Autodesk Fusion 360 part; units mm, degrees
(part 2 of 5)
sketch "Receiver conveyor side beam sketch (1)" plane through (0, 0, -180) normal (0, 0, 1) x (1, 0, 0) in component "MM28 Sliding receiver conveyor"
  line L0 (-2100, 164) -> (-930, 164)
  line L1 (-930, 164) -> (-930, 186)
  line L2 (-930, 186) -> (-2100, 186)
  line L3 (-2100, 186) -> (-2100, 164)
extrude "Receiver conveyor side beam (1)" add sketch "Receiver conveyor side beam sketch (1)" along normal blind 32 separate body makes body 68 in component "MM28 Sliding receiver conveyor"
ref_plane "WorkPlane3" through (0, -195, 0) normal (0, 1, 0) x (0, 0, 1) in component "MM28 Sliding receiver conveyor"
sketch "Receiver conveyor roller sketch" plane through (0, -195, 0) normal (0, 1, 0) x (1, 0, 0) in component "MM28 Sliding receiver conveyor"
  circle A0 centre (-2085, 136) radius 8
extrude "Receiver conveyor roller" add sketch "Receiver conveyor roller sketch" along normal blind 390 separate body makes body 69 in component "MM28 Sliding receiver conveyor"
ref_plane "WorkPlane4" through (0, -195, 0) normal (0, 1, 0) x (0, 0, 1) in component "MM28 Sliding receiver conveyor"
sketch "Receiver conveyor roller sketch (1)" plane through (0, -195, 0) normal (0, 1, 0) x (1, 0, 0) in component "MM28 Sliding receiver conveyor"
  circle A0 centre (-2025, 136) radius 8
extrude "Receiver conveyor roller (1)" add sketch "Receiver conveyor roller sketch (1)" along normal blind 390 separate body makes body 70 in component "MM28 Sliding receiver conveyor"
ref_plane "WorkPlane5" through (0, -195, 0) normal (0, 1, 0) x (0, 0, 1) in component "MM28 Sliding receiver conveyor"
sketch "Receiver conveyor roller sketch (2)" plane through (0, -195, 0) normal (0, 1, 0) x (1, 0, 0) in component "MM28 Sliding receiver conveyor"
  circle A0 centre (-1965, 136) radius 8
extrude "Receiver conveyor roller (2)" add sketch "Receiver conveyor roller sketch (2)" along normal blind 390 separate body makes body 71 in component "MM28 Sliding receiver conveyor"
ref_plane "WorkPlane6" through (0, -195, 0) normal (0, 1, 0) x (0, 0, 1) in component "MM28 Sliding receiver conveyor"
sketch "Receiver conveyor roller sketch (3)" plane through (0, -195, 0) normal (0, 1, 0) x (1, 0, 0) in component "MM28 Sliding receiver conveyor"
  circle A0 centre (-1905, 136) radius 8
extrude "Receiver conveyor roller (3)" add sketch "Receiver conveyor roller sketch (3)" along normal blind 390 separate body makes body 72 in component "MM28 Sliding receiver conveyor"
ref_plane "WorkPlane7" through (0, -195, 0) normal (0, 1, 0) x (0, 0, 1) in component "MM28 Sliding receiver conveyor"
sketch "Receiver conveyor roller sketch (4)" plane through (0, -195, 0) normal (0, 1, 0) x (1, 0, 0) in component "MM28 Sliding receiver conveyor"
  circle A0 centre (-1845, 136) radius 8
extrude "Receiver conveyor roller (4)" add sketch "Receiver conveyor roller sketch (4)" along normal blind 390 separate body makes body 73 in component "MM28 Sliding receiver conveyor"
ref_plane "WorkPlane8" through (0, -195, 0) normal (0, 1, 0) x (0, 0, 1) in component "MM28 Sliding receiver conveyor"
sketch "Receiver conveyor roller sketch (5)" plane through (0, -195, 0) normal (0, 1, 0) x (1, 0, 0) in component "MM28 Sliding receiver conveyor"
  circle A0 centre (-1785, 136) radius 8
extrude "Receiver conveyor roller (5)" add sketch "Receiver conveyor roller sketch (5)" along normal blind 390 separate body makes body 74 in component "MM28 Sliding receiver conveyor"
ref_plane "WorkPlane9" through (0, -195, 0) normal (0, 1, 0) x (0, 0, 1) in component "MM28 Sliding receiver conveyor"
sketch "Receiver conveyor roller sketch (6)" plane through (0, -195, 0) normal (0, 1, 0) x (1, 0, 0) in component "MM28 Sliding receiver conveyor"
  circle A0 centre (-1725, 136) radius 8
extrude "Receiver conveyor roller (6)" add sketch "Receiver conveyor roller sketch (6)" along normal blind 390 separate body makes body 75 in component "MM28 Sliding receiver conveyor"
ref_plane "WorkPlane10" through (0, -195, 0) normal (0, 1, 0) x (0, 0, 1) in component "MM28 Sliding receiver conveyor"
sketch "Receiver conveyor roller sketch (7)" plane through (0, -195, 0) normal (0, 1, 0) x (1, 0, 0) in component "MM28 Sliding receiver conveyor"
  circle A0 centre (-1665, 136) radius 8
extrude "Receiver conveyor roller (7)" add sketch "Receiver conveyor roller sketch (7)" along normal blind 390 separate body makes body 76 in component "MM28 Sliding receiver conveyor"
ref_plane "WorkPlane11" through (0, -195, 0) normal (0, 1, 0) x (0, 0, 1) in component "MM28 Sliding receiver conveyor"
sketch "Receiver conveyor roller sketch (8)" plane through (0, -195, 0) normal (0, 1, 0) x (1, 0, 0) in component "MM28 Sliding receiver conveyor"
  circle A0 centre (-1605, 136) radius 8
extrude "Receiver conveyor roller (8)" add sketch "Receiver conveyor roller sketch (8)" along normal blind 390 separate body makes body 77 in component "MM28 Sliding receiver conveyor"
ref_plane "WorkPlane12" through (0, -195, 0) normal (0, 1, 0) x (0, 0, 1) in component "MM28 Sliding receiver conveyor"
sketch "Receiver conveyor roller sketch (9)" plane through (0, -195, 0) normal (0, 1, 0) x (1, 0, 0) in component "MM28 Sliding receiver conveyor"
  circle A0 centre (-1545, 136) radius 8
extrude "Receiver conveyor roller (9)" add sketch "Receiver conveyor roller sketch (9)" along normal blind 390 separate body makes body 78 in component "MM28 Sliding receiver conveyor"
ref_plane "WorkPlane13" through (0, -195, 0) normal (0, 1, 0) x (0, 0, 1) in component "MM28 Sliding receiver conveyor"
sketch "Receiver conveyor roller sketch (10)" plane through (0, -195, 0) normal (0, 1, 0) x (1, 0, 0) in component "MM28 Sliding receiver conveyor"
  circle A0 centre (-1485, 136) radius 8
extrude "Receiver conveyor roller (10)" add sketch "Receiver conveyor roller sketch (10)" along normal blind 390 separate body makes body 79 in component "MM28 Sliding receiver conveyor"
ref_plane "WorkPlane14" through (0, -195, 0) normal (0, 1, 0) x (0, 0, 1) in component "MM28 Sliding receiver conveyor"
sketch "Receiver conveyor roller sketch (11)" plane through (0, -195, 0) normal (0, 1, 0) x (1, 0, 0) in component "MM28 Sliding receiver conveyor"
  circle A0 centre (-1425, 136) radius 8
extrude "Receiver conveyor roller (11)" add sketch "Receiver conveyor roller sketch (11)" along normal blind 390 separate body makes body 80 in component "MM28 Sliding receiver conveyor"
ref_plane "WorkPlane15" through (0, -195, 0) normal (0, 1, 0) x (0, 0, 1) in component "MM28 Sliding receiver conveyor"
sketch "Receiver conveyor roller sketch (12)" plane through (0, -195, 0) normal (0, 1, 0) x (1, 0, 0) in component "MM28 Sliding receiver conveyor"
  circle A0 centre (-1365, 136) radius 8
extrude "Receiver conveyor roller (12)" add sketch "Receiver conveyor roller sketch (12)" along normal blind 390 separate body makes body 81 in component "MM28 Sliding receiver conveyor"
ref_plane "WorkPlane16" through (0, -195, 0) normal (0, 1, 0) x (0, 0, 1) in component "MM28 Sliding receiver conveyor"
sketch "Receiver conveyor roller sketch (13)" plane through (0, -195, 0) normal (0, 1, 0) x (1, 0, 0) in component "MM28 Sliding receiver conveyor"
  circle A0 centre (-1305, 136) radius 8
extrude "Receiver conveyor roller (13)" add sketch "Receiver conveyor roller sketch (13)" along normal blind 390 separate body makes body 82 in component "MM28 Sliding receiver conveyor"
ref_plane "WorkPlane17" through (0, -195, 0) normal (0, 1, 0) x (0, 0, 1) in component "MM28 Sliding receiver conveyor"
sketch "Receiver conveyor roller sketch (14)" plane through (0, -195, 0) normal (0, 1, 0) x (1, 0, 0) in component "MM28 Sliding receiver conveyor"
  circle A0 centre (-1245, 136) radius 8
extrude "Receiver conveyor roller (14)" add sketch "Receiver conveyor roller sketch (14)" along normal blind 390 separate body makes body 83 in component "MM28 Sliding receiver conveyor"
ref_plane "WorkPlane18" through (0, -195, 0) normal (0, 1, 0) x (0, 0, 1) in component "MM28 Sliding receiver conveyor"
sketch "Receiver conveyor roller sketch (15)" plane through (0, -195, 0) normal (0, 1, 0) x (1, 0, 0) in component "MM28 Sliding receiver conveyor"
  circle A0 centre (-1185, 136) radius 8
extrude "Receiver conveyor roller (15)" add sketch "Receiver conveyor roller sketch (15)" along normal blind 390 separate body makes body 84 in component "MM28 Sliding receiver conveyor"
ref_plane "WorkPlane19" through (0, -195, 0) normal (0, 1, 0) x (0, 0, 1) in component "MM28 Sliding receiver conveyor"
sketch "Receiver conveyor roller sketch (16)" plane through (0, -195, 0) normal (0, 1, 0) x (1, 0, 0) in component "MM28 Sliding receiver conveyor"
  circle A0 centre (-1125, 136) radius 8
extrude "Receiver conveyor roller (16)" add sketch "Receiver conveyor roller sketch (16)" along normal blind 390 separate body makes body 85 in component "MM28 Sliding receiver conveyor"
ref_plane "WorkPlane20" through (0, -195, 0) normal (0, 1, 0) x (0, 0, 1) in component "MM28 Sliding receiver conveyor"
sketch "Receiver conveyor roller sketch (17)" plane through (0, -195, 0) normal (0, 1, 0) x (1, 0, 0) in component "MM28 Sliding receiver conveyor"
  circle A0 centre (-1065, 136) radius 8
extrude "Receiver conveyor roller (17)" add sketch "Receiver conveyor roller sketch (17)" along normal blind 390 separate body makes body 86 in component "MM28 Sliding receiver conveyor"
ref_plane "WorkPlane21" through (0, -195, 0) normal (0, 1, 0) x (0, 0, 1) in component "MM28 Sliding receiver conveyor"
sketch "Receiver conveyor roller sketch (18)" plane through (0, -195, 0) normal (0, 1, 0) x (1, 0, 0) in component "MM28 Sliding receiver conveyor"
  circle A0 centre (-1005, 136) radius 8
extrude "Receiver conveyor roller (18)" add sketch "Receiver conveyor roller sketch (18)" along normal blind 390 separate body makes body 87 in component "MM28 Sliding receiver conveyor"
ref_plane "WorkPlane22" through (0, -195, 0) normal (0, 1, 0) x (0, 0, 1) in component "MM28 Sliding receiver conveyor"
sketch "Receiver conveyor roller sketch (19)" plane through (0, -195, 0) normal (0, 1, 0) x (1, 0, 0) in component "MM28 Sliding receiver conveyor"
  circle A0 centre (-945, 136) radius 8
extrude "Receiver conveyor roller (19)" add sketch "Receiver conveyor roller sketch (19)" along normal blind 390 separate body makes body 88 in component "MM28 Sliding receiver conveyor"
ref_plane "WorkPlane23" through (0, 0, -175) normal (0, 0, 1) x (1, 0, 0) in component "MM28 Sliding receiver conveyor"
sketch "Receiver cross tie sketch" plane through (0, 0, -175) normal (0, 0, 1) x (1, 0, 0) in component "MM28 Sliding receiver conveyor"
  line L0 (-2062, -164) -> (-2038, -164)
  line L1 (-2038, -164) -> (-2038, 164)
  line L2 (-2038, 164) -> (-2062, 164)
  line L3 (-2062, 164) -> (-2062, -164)
extrude "Receiver cross tie" add sketch "Receiver cross tie sketch" along normal blind 22 separate body makes body 89 in component "MM28 Sliding receiver conveyor"
ref_plane "WorkPlane24" through (0, 0, -175) normal (0, 0, 1) x (1, 0, 0) in component "MM28 Sliding receiver conveyor"
sketch "Receiver cross tie sketch (1)" plane through (0, 0, -175) normal (0, 0, 1) x (1, 0, 0) in component "MM28 Sliding receiver conveyor"
  line L0 (-1542, -164) -> (-1518, -164)
  line L1 (-1518, -164) -> (-1518, 164)
  line L2 (-1518, 164) -> (-1542, 164)
  line L3 (-1542, 164) -> (-1542, -164)
extrude "Receiver cross tie (1)" add sketch "Receiver cross tie sketch (1)" along normal blind 22 separate body makes body 90 in component "MM28 Sliding receiver conveyor"
ref_plane "WorkPlane25" through (0, 0, -175) normal (0, 0, 1) x (1, 0, 0) in component "MM28 Sliding receiver conveyor"
sketch "Receiver cross tie sketch (2)" plane through (0, 0, -175) normal (0, 0, 1) x (1, 0, 0) in component "MM28 Sliding receiver conveyor"
  line L0 (-1002, -164) -> (-978, -164)
  line L1 (-978, -164) -> (-978, 164)
  line L2 (-978, 164) -> (-1002, 164)
  line L3 (-1002, 164) -> (-1002, -164)
extrude "Receiver cross tie (2)" add sketch "Receiver cross tie sketch (2)" along normal blind 22 separate body makes body 91 in component "MM28 Sliding receiver conveyor"
ref_plane "WorkPlane1" through (0, 0, -340) normal (0, 0, 1) x (1, 0, 0) in component "MM13 Battery module 2 kWh -300"
sketch "Battery hardware envelope sketch" plane through (0, 0, -340) normal (0, 0, 1) x (1, 0, 0) in component "MM13 Battery module 2 kWh -300"
  line L0 (960, -420) -> (1140, -420)
  line L1 (1140, -420) -> (1140, -180)
  line L2 (1140, -180) -> (960, -180)
  line L3 (960, -180) -> (960, -420)
extrude "Battery hardware envelope" add sketch "Battery hardware envelope sketch" along normal blind 360 separate body makes body 92 in component "MM13 Battery module 2 kWh -300"
ref_plane "WorkPlane1" through (0, 0, -340) normal (0, 0, 1) x (1, 0, 0) in component "MM13 Battery module 2 kWh 300"
sketch "Battery hardware envelope sketch (2)" plane through (0, 0, -340) normal (0, 0, 1) x (1, 0, 0) in component "MM13 Battery module 2 kWh 300"
  line L0 (960, 180) -> (1140, 180)
  line L1 (1140, 180) -> (1140, 420)
  line L2 (1140, 420) -> (960, 420)
  line L3 (960, 420) -> (960, 180)
extrude "Battery hardware envelope'" add sketch "Battery hardware envelope sketch (2)" along normal blind 360 separate body makes body 93 in component "MM13 Battery module 2 kWh 300"
ref_plane "WorkPlane1" through (0, 0, 200) normal (0, 0, 1) x (1, 0, 0) in component "MM14 Pressure temperature and power electronics"
sketch "Controller and redundant logger envelope sketch" plane through (0, 0, 200) normal (0, 0, 1) x (1, 0, 0) in component "MM14 Pressure temperature and power electronics"
  line L0 (980, -150) -> (1160, -150)
  line L1 (1160, -150) -> (1160, 150)
  line L2 (1160, 150) -> (980, 150)
  line L3 (980, 150) -> (980, -150)
extrude "Controller and redundant logger envelope" add sketch "Controller and redundant logger envelope sketch" along normal blind 160 separate body makes body 94 in component "MM14 Pressure temperature and power electronics"
ref_plane "WorkPlane2" through (1160, 0, 0) normal (1, 0, 0) x (0, 1, 0) in component "MM14 Pressure temperature and power electronics"
sketch "Sealed electrical connector sketch" plane through (1160, 0, 0) normal (1, 0, 0) x (0, 0, -1) in component "MM14 Pressure temperature and power electronics"
  circle A0 centre (-280, -100) radius 14
extrude "Sealed electrical connector" add sketch "Sealed electrical connector sketch" along normal blind 60 separate body makes body 95 in component "MM14 Pressure temperature and power electronics"
ref_plane "WorkPlane3" through (1160, 0, 0) normal (1, 0, 0) x (0, 1, 0) in component "MM14 Pressure temperature and power electronics"
sketch "Sealed electrical connector sketch (1)" plane through (1160, 0, 0) normal (1, 0, 0) x (0, 0, -1) in component "MM14 Pressure temperature and power electronics"
  circle A0 centre (-280, 100) radius 14
extrude "Sealed electrical connector (1)" add sketch "Sealed electrical connector sketch (1)" along normal blind 60 separate body makes body 96 in component "MM14 Pressure temperature and power electronics"
ref_plane "WorkPlane1" through (0, 0, -510) normal (0, 0, 1) x (1, 0, 0) in component "MM15 Equalization isolation and relief manifold"
sketch "Clean side valve manifold sketch" plane through (0, 0, -510) normal (0, 0, 1) x (1, 0, 0) in component "MM15 Equalization isolation and relief manifold"
  line L0 (-1270, -120) -> (-1090, -120)
  line L1 (-1090, -120) -> (-1090, 120)
  line L2 (-1090, 120) -> (-1270, 120)
  line L3 (-1270, 120) -> (-1270, -120)
extrude "Clean side valve manifold" add sketch "Clean side valve manifold sketch" along normal blind 100 separate body makes body 97 in component "MM15 Equalization isolation and relief manifold"
ref_plane "WorkPlane2" through (-1280, 0, 0) normal (1, 0, 0) x (0, 1, 0) in component "MM15 Equalization isolation and relief manifold"
sketch "Dual equalization valve envelope sketch" plane through (-1280, 0, 0) normal (1, 0, 0) x (0, 0, -1) in component "MM15 Equalization isolation and relief manifold"
  circle A0 centre (460, -70) radius 18
extrude "Dual equalization valve envelope" add sketch "Dual equalization valve envelope sketch" along normal blind 220 separate body makes body 98 in component "MM15 Equalization isolation and relief manifold"
ref_plane "WorkPlane3" through (-1280, 0, 0) normal (1, 0, 0) x (0, 1, 0) in component "MM15 Equalization isolation and relief manifold"
sketch "Dual equalization valve envelope sketch (1)" plane through (-1280, 0, 0) normal (1, 0, 0) x (0, 0, -1) in component "MM15 Equalization isolation and relief manifold"
  circle A0 centre (460, 70) radius 18
extrude "Dual equalization valve envelope (1)" add sketch "Dual equalization valve envelope sketch (1)" along normal blind 220 separate body makes body 99 in component "MM15 Equalization isolation and relief manifold"
ref_plane "WorkPlane1" through (0, 0, -1050) normal (0, 0, 1) x (1, 0, 0) in component "MM20 Cargo trolley chassis"
sketch "Longitudinal chassis tube sketch" plane through (0, 0, -1050) normal (0, 0, 1) x (1, 0, 0) in component "MM20 Cargo trolley chassis"
  line L0 (-1275, -800) -> (1275, -800)
  line L1 (1275, -800) -> (1275, -720)
  line L2 (1275, -720) -> (-1275, -720)
  line L3 (-1275, -720) -> (-1275, -800)
  line L4 (-1235, -785) -> (1235, -785)
  line L5 (1235, -785) -> (1235, -735)
  line L6 (1235, -735) -> (-1235, -735)
  line L7 (-1235, -735) -> (-1235, -785)
extrude "Longitudinal chassis tube" add sketch "Longitudinal chassis tube sketch" along normal blind 60 separate body makes body 100 in component "MM20 Cargo trolley chassis"
ref_plane "WorkPlane2" through (0, 0, -1050) normal (0, 0, 1) x (1, 0, 0) in component "MM20 Cargo trolley chassis"
sketch "Longitudinal chassis tube sketch (1)" plane through (0, 0, -1050) normal (0, 0, 1) x (1, 0, 0) in component "MM20 Cargo trolley chassis"
  line L0 (-1275, 720) -> (1275, 720)
  line L1 (1275, 720) -> (1275, 800)
  line L2 (1275, 800) -> (-1275, 800)
  line L3 (-1275, 800) -> (-1275, 720)
  line L4 (-1235, 735) -> (1235, 735)
  line L5 (1235, 735) -> (1235, 785)
  line L6 (1235, 785) -> (-1235, 785)
  line L7 (-1235, 785) -> (-1235, 735)
extrude "Longitudinal chassis tube (1)" add sketch "Longitudinal chassis tube sketch (1)" along normal blind 60 separate body makes body 101 in component "MM20 Cargo trolley chassis"
ref_plane "WorkPlane3" through (0, 0, -1050) normal (0, 0, 1) x (1, 0, 0) in component "MM20 Cargo trolley chassis"
sketch "Cross frame tube sketch" plane through (0, 0, -1050) normal (0, 0, 1) x (1, 0, 0) in component "MM20 Cargo trolley chassis"
  line L0 (-1090, -840) -> (-1010, -840)
  line L1 (-1010, -840) -> (-1010, 840)
  line L2 (-1010, 840) -> (-1090, 840)
  line L3 (-1090, 840) -> (-1090, -840)
  line L4 (-1075, -800) -> (-1025, -800)
  line L5 (-1025, -800) -> (-1025, 800)
  line L6 (-1025, 800) -> (-1075, 800)
  line L7 (-1075, 800) -> (-1075, -800)
extrude "Cross frame tube" add sketch "Cross frame tube sketch" along normal blind 60 separate body makes body 102 in component "MM20 Cargo trolley chassis"
ref_plane "WorkPlane4" through (0, 0, -1050) normal (0, 0, 1) x (1, 0, 0) in component "MM20 Cargo trolley chassis"
sketch "Cross frame tube sketch (1)" plane through (0, 0, -1050) normal (0, 0, 1) x (1, 0, 0) in component "MM20 Cargo trolley chassis"
  line L0 (-40, -840) -> (40, -840)
  line L1 (40, -840) -> (40, 840)
  line L2 (40, 840) -> (-40, 840)
  line L3 (-40, 840) -> (-40, -840)
  line L4 (-25, -800) -> (25, -800)
  line L5 (25, -800) -> (25, 800)
  line L6 (25, 800) -> (-25, 800)
  line L7 (-25, 800) -> (-25, -800)
extrude "Cross frame tube (1)" add sketch "Cross frame tube sketch (1)" along normal blind 60 separate body makes body 103 in component "MM20 Cargo trolley chassis"
ref_plane "WorkPlane5" through (0, 0, -1050) normal (0, 0, 1) x (1, 0, 0) in component "MM20 Cargo trolley chassis"
sketch "Cross frame tube sketch (2)" plane through (0, 0, -1050) normal (0, 0, 1) x (1, 0, 0) in component "MM20 Cargo trolley chassis"
  line L0 (1010, -840) -> (1090, -840)
  line L1 (1090, -840) -> (1090, 840)
  line L2 (1090, 840) -> (1010, 840)
  line L3 (1010, 840) -> (1010, -840)
  line L4 (1025, -800) -> (1075, -800)
  line L5 (1075, -800) -> (1075, 800)
  line L6 (1075, 800) -> (1025, 800)
  line L7 (1025, 800) -> (1025, -800)
extrude "Cross frame tube (2)" add sketch "Cross frame tube sketch (2)" along normal blind 60 separate body makes body 104 in component "MM20 Cargo trolley chassis"
ref_plane "WorkPlane6" through (0, 0, -990) normal (0, 0, 1) x (1, 0, 0) in component "MM20 Cargo trolley chassis"
sketch "Quick lock carrier saddle sketch" plane through (0, 0, -990) normal (0, 0, 1) x (1, 0, 0) in component "MM20 Cargo trolley chassis"
  line L0 (-735, -680) -> (-565, -680)
  line L1 (-565, -680) -> (-565, -540)
  line L2 (-565, -540) -> (-735, -540)
  line L3 (-735, -540) -> (-735, -680)
extrude "Quick lock carrier saddle" add sketch "Quick lock carrier saddle sketch" along normal blind 240 separate body makes body 105 in component "MM20 Cargo trolley chassis"
ref_plane "WorkPlane7" through (0, 0, -990) normal (0, 0, 1) x (1, 0, 0) in component "MM20 Cargo trolley chassis"
sketch "Quick lock carrier saddle sketch (1)" plane through (0, 0, -990) normal (0, 0, 1) x (1, 0, 0) in component "MM20 Cargo trolley chassis"
  line L0 (-735, 540) -> (-565, 540)
  line L1 (-565, 540) -> (-565, 680)
  line L2 (-565, 680) -> (-735, 680)
  line L3 (-735, 680) -> (-735, 540)
extrude "Quick lock carrier saddle (1)" add sketch "Quick lock carrier saddle sketch (1)" along normal blind 240 separate body makes body 106 in component "MM20 Cargo trolley chassis"
ref_plane "WorkPlane8" through (0, 0, -990) normal (0, 0, 1) x (1, 0, 0) in component "MM20 Cargo trolley chassis"
sketch "Quick lock carrier saddle sketch (2)" plane through (0, 0, -990) normal (0, 0, 1) x (1, 0, 0) in component "MM20 Cargo trolley chassis"
  line L0 (565, -680) -> (735, -680)
  line L1 (735, -680) -> (735, -540)
  line L2 (735, -540) -> (565, -540)
  line L3 (565, -540) -> (565, -680)
extrude "Quick lock carrier saddle (2)" add sketch "Quick lock carrier saddle sketch (2)" along normal blind 240 separate body makes body 107 in component "MM20 Cargo trolley chassis"
ref_plane "WorkPlane9" through (0, 0, -990) normal (0, 0, 1) x (1, 0, 0) in component "MM20 Cargo trolley chassis"
sketch "Quick lock carrier saddle sketch (3)" plane through (0, 0, -990) normal (0, 0, 1) x (1, 0, 0) in component "MM20 Cargo trolley chassis"
  line L0 (565, 540) -> (735, 540)
  line L1 (735, 540) -> (735, 680)
  line L2 (735, 680) -> (565, 680)
  line L3 (565, 680) -> (565, 540)
extrude "Quick lock carrier saddle (3)" add sketch "Quick lock carrier saddle sketch (3)" along normal blind 240 separate body makes body 108 in component "MM20 Cargo trolley chassis"
ref_plane "WorkPlane1" through (0, -90, 0) normal (0, 1, 0) x (0, 0, 1) in component "MM21 Compliant wheel envelope"
sketch "Open wheel tread sketch" plane through (0, -90, 0) normal (0, 1, 0) x (1, 0, 0) in component "MM21 Compliant wheel envelope"
  circle A0 centre (0, 0) radius 250
  circle A1 centre (0, 0) radius 230
extrude "Open wheel tread" add sketch "Open wheel tread sketch" along normal blind 180 separate body makes body 109 in component "MM21 Compliant wheel envelope"
ref_plane "WorkPlane2" through (0, -110, 0) normal (0, 1, 0) x (0, 0, 1) in component "MM21 Compliant wheel envelope"
sketch "Wheel hub sketch" plane through (0, -110, 0) normal (0, 1, 0) x (1, 0, 0) in component "MM21 Compliant wheel envelope"
  circle A0 centre (0, 0) radius 65
  circle A1 centre (0, 0) radius 25
extrude "Wheel hub" add sketch "Wheel hub sketch" along normal blind 220 separate body makes body 110 in component "MM21 Compliant wheel envelope"
ref_plane "WorkPlane3" through (0, -5, 0) normal (0, 1, 0) x (0, 0, 1) in component "MM21 Compliant wheel envelope"
sketch "Ten radial spoke profiles" plane through (0, -5, 0) normal (0, 1, 0) x (1, 0, 0) in component "MM21 Compliant wheel envelope"
  line L0 (65, 6) -> (230, 6)
  line L1 (230, 6) -> (230, -6)
  line L2 (230, -6) -> (65, -6)
  line L3 (65, -6) -> (65, 6)
  line L4 (56.1128, -33.3519) -> (189.6006, -130.3365)
  line L5 (189.6006, -130.3365) -> (182.5472, -140.0447)
  line L6 (182.5472, -140.0447) -> (49.0594, -43.0601)
  line L7 (49.0594, -43.0601) -> (56.1128, -33.3519)
  line L8 (25.7924, -59.9646) -> (76.7802, -216.8889)
  line L9 (76.7802, -216.8889) -> (65.3676, -220.5971)
  line L10 (65.3676, -220.5971) -> (14.3798, -63.6728)
  line L11 (14.3798, -63.6728) -> (25.7924, -59.9646)
  line L12 (-14.3798, -63.6728) -> (-65.3676, -220.5971)
  line L13 (-65.3676, -220.5971) -> (-76.7802, -216.8889)
  line L14 (-76.7802, -216.8889) -> (-25.7924, -59.9646)
  line L15 (-25.7924, -59.9646) -> (-14.3798, -63.6728)
  line L16 (-49.0594, -43.0601) -> (-182.5472, -140.0447)
  line L17 (-182.5472, -140.0447) -> (-189.6006, -130.3365)
  line L18 (-189.6006, -130.3365) -> (-56.1128, -33.3519)
  line L19 (-56.1128, -33.3519) -> (-49.0594, -43.0601)
  line L20 (-65, -6) -> (-230, -6)
  line L21 (-230, -6) -> (-230, 6)
  line L22 (-230, 6) -> (-65, 6)
  line L23 (-65, 6) -> (-65, -6)
  line L24 (-56.1128, 33.3519) -> (-189.6006, 130.3365)
  line L25 (-189.6006, 130.3365) -> (-182.5472, 140.0447)
  line L26 (-182.5472, 140.0447) -> (-49.0594, 43.0601)
  line L27 (-49.0594, 43.0601) -> (-56.1128, 33.3519)
  line L28 (-25.7924, 59.9646) -> (-76.7802, 216.8889)
  line L29 (-76.7802, 216.8889) -> (-65.3676, 220.5971)
  line L30 (-65.3676, 220.5971) -> (-14.3798, 63.6728)
  line L31 (-14.3798, 63.6728) -> (-25.7924, 59.9646)
  line L32 (14.3798, 63.6728) -> (65.3676, 220.5971)
  line L33 (65.3676, 220.5971) -> (76.7802, 216.8889)
  line L34 (76.7802, 216.8889) -> (25.7924, 59.9646)
  line L35 (25.7924, 59.9646) -> (14.3798, 63.6728)
  line L36 (49.0594, 43.0601) -> (182.5472, 140.0447)
  line L37 (182.5472, 140.0447) -> (189.6006, 130.3365)
  line L38 (189.6006, 130.3365) -> (56.1128, 33.3519)
  line L39 (56.1128, 33.3519) -> (49.0594, 43.0601)
extrude "Mesh spoke envelope" add sketch "Ten radial spoke profiles" against normal blind 10 separate body contours L0 L1 L2 L3 makes body 111 in component "MM21 Compliant wheel envelope"
extrude "Mesh spoke envelope (1)" add sketch "Ten radial spoke profiles" against normal blind 10 separate body contours L20 L21 L22 L23 makes body 112 in component "MM21 Compliant wheel envelope"
extrude "Mesh spoke envelope (2)" add sketch "Ten radial spoke profiles" against normal blind 10 separate body contours L16 L17 L18 L19 makes body 113 in component "MM21 Compliant wheel envelope"
extrude "Mesh spoke envelope (3)" add sketch "Ten radial spoke profiles" against normal blind 10 separate body contours L24 L25 L26 L27 makes body 114 in component "MM21 Compliant wheel envelope"
extrude "Mesh spoke envelope (4)" add sketch "Ten radial spoke profiles" against normal blind 10 separate body contours L12 L13 L14 L15 makes body 115 in component "MM21 Compliant wheel envelope"
extrude "Mesh spoke envelope (5)" add sketch "Ten radial spoke profiles" against normal blind 10 separate body contours L28 L29 L30 L31 makes body 116 in component "MM21 Compliant wheel envelope"
extrude "Mesh spoke envelope (6)" add sketch "Ten radial spoke profiles" against normal blind 10 separate body contours L8 L9 L10 L11 makes body 117 in component "MM21 Compliant wheel envelope"
extrude "Mesh spoke envelope (7)" add sketch "Ten radial spoke profiles" against normal blind 10 separate body contours L32 L33 L34 L35 makes body 118 in component "MM21 Compliant wheel envelope"
extrude "Mesh spoke envelope (8)" add sketch "Ten radial spoke profiles" against normal blind 10 separate body contours L4 L5 L6 L7 makes body 119 in component "MM21 Compliant wheel envelope"
extrude "Mesh spoke envelope (9)" add sketch "Ten radial spoke profiles" against normal blind 10 separate body contours L36 L37 L38 L39 makes body 120 in component "MM21 Compliant wheel envelope"
ref_plane "WorkPlane1" through (0, -850, 0) normal (0, 1, 0) x (0, 0, 1) in component "MM22 Drive motors brakes and bogie envelopes"
sketch "Drive and brake envelope sketch" plane through (0, -850, 0) normal (0, 1, 0) x (1, 0, 0) in component "MM22 Drive motors brakes and bogie envelopes"
  circle A0 centre (-1050, 1270) radius 80
extrude "Drive and brake envelope" add sketch "Drive and brake envelope sketch" against normal blind 100 separate body makes body 121 in component "MM22 Drive motors brakes and bogie envelopes"
ref_plane "WorkPlane2" through (0, 0, -1260) normal (0, 0, 1) x (1, 0, 0) in component "MM22 Drive motors brakes and bogie envelopes"
sketch "Bogie support envelope sketch" plane through (0, 0, -1260) normal (0, 0, 1) x (1, 0, 0) in component "MM22 Drive motors brakes and bogie envelopes"
  line L0 (-1100, -830) -> (-1000, -830)
  line L1 (-1000, -830) -> (-1000, -730)
  line L2 (-1000, -730) -> (-1100, -730)
  line L3 (-1100, -730) -> (-1100, -830)
extrude "Bogie support envelope" add sketch "Bogie support envelope sketch" along normal blind 240 separate body makes body 122 in component "MM22 Drive motors brakes and bogie envelopes"
ref_plane "WorkPlane3" through (0, 850, 0) normal (0, 1, 0) x (0, 0, 1) in component "MM22 Drive motors brakes and bogie envelopes"
sketch "Drive and brake envelope sketch (1)" plane through (0, 850, 0) normal (0, 1, 0) x (1, 0, 0) in component "MM22 Drive motors brakes and bogie envelopes"
  circle A0 centre (-1050, 1270) radius 80
extrude "Drive and brake envelope (1)" add sketch "Drive and brake envelope sketch (1)" along normal blind 100 separate body makes body 123 in component "MM22 Drive motors brakes and bogie envelopes"
ref_plane "WorkPlane4" through (0, 0, -1260) normal (0, 0, 1) x (1, 0, 0) in component "MM22 Drive motors brakes and bogie envelopes"
sketch "Bogie support envelope sketch (1)" plane through (0, 0, -1260) normal (0, 0, 1) x (1, 0, 0) in component "MM22 Drive motors brakes and bogie envelopes"
  line L0 (-1100, 730) -> (-1000, 730)
  line L1 (-1000, 730) -> (-1000, 830)
  line L2 (-1000, 830) -> (-1100, 830)
  line L3 (-1100, 830) -> (-1100, 730)
extrude "Bogie support envelope (1)" add sketch "Bogie support envelope sketch (1)" along normal blind 240 separate body makes body 124 in component "MM22 Drive motors brakes and bogie envelopes"
ref_plane "WorkPlane5" through (0, -850, 0) normal (0, 1, 0) x (0, 0, 1) in component "MM22 Drive motors brakes and bogie envelopes"
sketch "Drive and brake envelope sketch (2)" plane through (0, -850, 0) normal (0, 1, 0) x (1, 0, 0) in component "MM22 Drive motors brakes and bogie envelopes"
  circle A0 centre (0, 1270) radius 80
extrude "Drive and brake envelope (2)" add sketch "Drive and brake envelope sketch (2)" against normal blind 100 separate body makes body 125 in component "MM22 Drive motors brakes and bogie envelopes"
ref_plane "WorkPlane6" through (0, 0, -1260) normal (0, 0, 1) x (1, 0, 0) in component "MM22 Drive motors brakes and bogie envelopes"
sketch "Bogie support envelope sketch (2)" plane through (0, 0, -1260) normal (0, 0, 1) x (1, 0, 0) in component "MM22 Drive motors brakes and bogie envelopes"
  line L0 (-50, -830) -> (50, -830)
  line L1 (50, -830) -> (50, -730)
  line L2 (50, -730) -> (-50, -730)
  line L3 (-50, -730) -> (-50, -830)
extrude "Bogie support envelope (2)" add sketch "Bogie support envelope sketch (2)" along normal blind 240 separate body makes body 126 in component "MM22 Drive motors brakes and bogie envelopes"
ref_plane "WorkPlane7" through (0, 850, 0) normal (0, 1, 0) x (0, 0, 1) in component "MM22 Drive motors brakes and bogie envelopes"
sketch "Drive and brake envelope sketch (3)" plane through (0, 850, 0) normal (0, 1, 0) x (1, 0, 0) in component "MM22 Drive motors brakes and bogie envelopes"
  circle A0 centre (0, 1270) radius 80
extrude "Drive and brake envelope (3)" add sketch "Drive and brake envelope sketch (3)" along normal blind 100 separate body makes body 127 in component "MM22 Drive motors brakes and bogie envelopes"
ref_plane "WorkPlane8" through (0, 0, -1260) normal (0, 0, 1) x (1, 0, 0) in component "MM22 Drive motors brakes and bogie envelopes"
sketch "Bogie support envelope sketch (3)" plane through (0, 0, -1260) normal (0, 0, 1) x (1, 0, 0) in component "MM22 Drive motors brakes and bogie envelopes"
  line L0 (-50, 730) -> (50, 730)
  line L1 (50, 730) -> (50, 830)
  line L2 (50, 830) -> (-50, 830)
  line L3 (-50, 830) -> (-50, 730)
extrude "Bogie support envelope (3)" add sketch "Bogie support envelope sketch (3)" along normal blind 240 separate body makes body 128 in component "MM22 Drive motors brakes and bogie envelopes"
ref_plane "WorkPlane9" through (0, -850, 0) normal (0, 1, 0) x (0, 0, 1) in component "MM22 Drive motors brakes and bogie envelopes"
sketch "Drive and brake envelope sketch (4)" plane through (0, -850, 0) normal (0, 1, 0) x (1, 0, 0) in component "MM22 Drive motors brakes and bogie envelopes"
  circle A0 centre (1050, 1270) radius 80
extrude "Drive and brake envelope (4)" add sketch "Drive and brake envelope sketch (4)" against normal blind 100 separate body makes body 129 in component "MM22 Drive motors brakes and bogie envelopes"
ref_plane "WorkPlane10" through (0, 0, -1260) normal (0, 0, 1) x (1, 0, 0) in component "MM22 Drive motors brakes and bogie envelopes"
sketch "Bogie support envelope sketch (4)" plane through (0, 0, -1260) normal (0, 0, 1) x (1, 0, 0) in component "MM22 Drive motors brakes and bogie envelopes"
  line L0 (1000, -830) -> (1100, -830)
  line L1 (1100, -830) -> (1100, -730)
  line L2 (1100, -730) -> (1000, -730)
  line L3 (1000, -730) -> (1000, -830)
extrude "Bogie support envelope (4)" add sketch "Bogie support envelope sketch (4)" along normal blind 240 separate body makes body 130 in component "MM22 Drive motors brakes and bogie envelopes"
ref_plane "WorkPlane11" through (0, 850, 0) normal (0, 1, 0) x (0, 0, 1) in component "MM22 Drive motors brakes and bogie envelopes"
sketch "Drive and brake envelope sketch (5)" plane through (0, 850, 0) normal (0, 1, 0) x (1, 0, 0) in component "MM22 Drive motors brakes and bogie envelopes"
  circle A0 centre (1050, 1270) radius 80
extrude "Drive and brake envelope (5)" add sketch "Drive and brake envelope sketch (5)" along normal blind 100 separate body makes body 131 in component "MM22 Drive motors brakes and bogie envelopes"
ref_plane "WorkPlane12" through (0, 0, -1260) normal (0, 0, 1) x (1, 0, 0) in component "MM22 Drive motors brakes and bogie envelopes"
sketch "Bogie support envelope sketch (5)" plane through (0, 0, -1260) normal (0, 0, 1) x (1, 0, 0) in component "MM22 Drive motors brakes and bogie envelopes"
  line L0 (1000, 730) -> (1100, 730)
  line L1 (1100, 730) -> (1100, 830)
  line L2 (1100, 830) -> (1000, 830)
  line L3 (1000, 830) -> (1000, 730)
extrude "Bogie support envelope (5)" add sketch "Bogie support envelope sketch (5)" along normal blind 240 separate body makes body 132 in component "MM22 Drive motors brakes and bogie envelopes"
ref_plane "WorkPlane1" through (0, 0, -1220) normal (0, 0, 1) x (1, 0, 0) in component "MM23 Trolley power and control"
sketch "4 kWh trolley battery and controller envelope sketch" plane through (0, 0, -1220) normal (0, 0, 1) x (1, 0, 0) in component "MM23 Trolley power and control"
  line L0 (500, -225) -> (1100, -225)
  line L1 (1100, -225) -> (1100, 225)
  line L2 (1100, 225) -> (500, 225)
  line L3 (500, 225) -> (500, -225)
extrude "4 kWh trolley battery and controller envelope" add sketch "4 kWh trolley battery and controller envelope sketch" along normal blind 180 separate body makes body 133 in component "MM23 Trolley power and control"
ref_plane "WorkPlane1" through (-2300, 0, 0) normal (1, 0, 0) x (0, 1, 0) in component "MM30 Rover habitat berthing adapter"
sketch "Receiver transfer tunnel sketch" plane through (-2300, 0, 0) normal (1, 0, 0) x (0, 0, -1) in component "MM30 Rover habitat berthing adapter"
  circle A0 centre (0, 0) radius 455
  circle A1 centre (0, 0) radius 450
extrude "Receiver transfer tunnel" add sketch "Receiver transfer tunnel sketch" along normal blind 660 separate body makes body 134 in component "MM30 Rover habitat berthing adapter"
ref_plane "WorkPlane2" through (-1640, 0, 0) normal (1, 0, 0) x (0, 1, 0) in component "MM30 Rover habitat berthing adapter"
sketch "Receiver common interface sketch" plane through (-1640, 0, 0) normal (1, 0, 0) x (0, 0, -1) in component "MM30 Rover habitat berthing adapter"
  circle A0 centre (0, 0) radius 530
extrude "Receiver common interface" add sketch "Receiver common interface sketch" along normal blind 20 separate body makes body 135 in component "MM30 Rover habitat berthing adapter"
ref_plane "WorkPlane3" through (0, 0, -235) normal (0, 0, 1) x (1, 0, 0) in component "MM30 Rover habitat berthing adapter"
sketch "Receiver hatch opening sketch" plane through (0, 0, -235) normal (0, 0, 1) x (1, 0, 0) in component "MM30 Rover habitat berthing adapter"
  line L0 (-1665, -335) -> (-1595, -335)
  line L1 (-1595, -335) -> (-1595, 335)
  line L2 (-1595, 335) -> (-1665, 335)
  line L3 (-1665, 335) -> (-1665, -335)
extrude "Receiver hatch opening" cut sketch "Receiver hatch opening sketch" along normal blind 470 bodies 134 135 in component "MM30 Rover habitat berthing adapter"
sketch "OPEN PRESSURE HATCH axis" plane through (0, 0, 0) normal (0, 0, 1) x (1, 0, 0) in component "MM01 Pressure shell and neck"
  point P0 (-1565, -375)
sketch "OPEN DUST SHIELD axis" plane through (0, 0, 0) normal (0, 0, 1) x (1, 0, 0) in component "MM01 Pressure shell and neck"
  point P0 (-1656, 570)
sketch "Sketch6" plane through (0, 0, 0) normal (0, 0, 1) x (1, 0, 0) in component "MM01 Pressure shell and neck"
sketch "Sketch7" plane through (0, 0, 0) normal (0, 0, 1) x (1, 0, 0) in component "MM01 Pressure shell and neck"
sketch "Sketch8" plane through (0, 0, 0) normal (0, 0, 1) x (1, 0, 0) in component "MM01 Pressure shell and neck"
sketch "Sketch9" plane through (0, 0, 0) normal (0, 0, 1) x (1, 0, 0) in component "MM01 Pressure shell and neck"
sketch "Sketch10" plane through (0, 0, 0) normal (0, 0, 1) x (1, 0, 0) in component "MM01 Pressure shell and neck"
ref_plane "WorkPlane1" through (0, 0, -780) normal (0, 0, 1) x (1, 0, 0) in component "MM12 Fixed elevator Z guides"
sketch "Fixed Z guide sketch" plane through (0, 0, -780) normal (0, 0, 1) x (1, 0, 0) in component "MM12 Fixed elevator Z guides"
  line L0 (-930, -475) -> (-900, -475)
  line L1 (-900, -475) -> (-900, -445)
  line L2 (-900, -445) -> (-930, -445)
  line L3 (-930, -445) -> (-930, -475)
extrude "Fixed Z guide" add sketch "Fixed Z guide sketch" along normal blind 1240 separate body makes body 136 in component "MM12 Fixed elevator Z guides"
ref_plane "WorkPlane2" through (0, 0, -780) normal (0, 0, 1) x (1, 0, 0) in component "MM12 Fixed elevator Z guides"
sketch "Fixed Z guide sketch (1)" plane through (0, 0, -780) normal (0, 0, 1) x (1, 0, 0) in component "MM12 Fixed elevator Z guides"
  line L0 (-930, 445) -> (-900, 445)
  line L1 (-900, 445) -> (-900, 475)
  line L2 (-900, 475) -> (-930, 475)
  line L3 (-930, 475) -> (-930, 445)
extrude "Fixed Z guide (1)" add sketch "Fixed Z guide sketch (1)" along normal blind 1240 separate body makes body 137 in component "MM12 Fixed elevator Z guides"
ref_plane "WorkPlane1" through (0, 0, -205) normal (0, 0, 1) x (1, 0, 0) in component "MM24 Elevator Z crossbeam"
sketch "Y traverse beam sketch" plane through (0, 0, -205) normal (0, 0, 1) x (1, 0, 0) in component "MM24 Elevator Z crossbeam"
  line L0 (-814, -480) -> (-782, -480)
  line L1 (-782, -480) -> (-782, 480)
  line L2 (-782, 480) -> (-814, 480)
  line L3 (-814, 480) -> (-814, -480)
extrude "Y traverse beam" add sketch "Y traverse beam sketch" along normal blind 40 separate body makes body 138 in component "MM24 Elevator Z crossbeam"
ref_plane "WorkPlane2" through (0, 0, -217.5) normal (0, 0, 1) x (1, 0, 0) in component "MM24 Elevator Z crossbeam"
sketch "Z bearing shoe sketch" plane through (0, 0, -217.5) normal (0, 0, 1) x (1, 0, 0) in component "MM24 Elevator Z crossbeam"
  line L0 (-900, -485) -> (-814, -485)
  line L1 (-814, -485) -> (-814, -435)
  line L2 (-814, -435) -> (-900, -435)
  line L3 (-900, -435) -> (-900, -485)
extrude "Z bearing shoe" add sketch "Z bearing shoe sketch" along normal blind 65 separate body makes body 139 in component "MM24 Elevator Z crossbeam"
ref_plane "WorkPlane3" through (0, 0, -217.5) normal (0, 0, 1) x (1, 0, 0) in component "MM24 Elevator Z crossbeam"
sketch "Z bearing shoe sketch (1)" plane through (0, 0, -217.5) normal (0, 0, 1) x (1, 0, 0) in component "MM24 Elevator Z crossbeam"
  line L0 (-900, 435) -> (-814, 435)
  line L1 (-814, 435) -> (-814, 485)
  line L2 (-814, 485) -> (-900, 485)
  line L3 (-900, 485) -> (-900, 435)
extrude "Z bearing shoe (1)" add sketch "Z bearing shoe sketch (1)" along normal blind 65 separate body makes body 140 in component "MM24 Elevator Z crossbeam"
ref_plane "WorkPlane1" through (0, 0, -155) normal (0, 0, 1) x (1, 0, 0) in component "MM25 Y carriage and powered receiving deck"
sketch "Receiving deck side support sketch" plane through (0, 0, -155) normal (0, 0, 1) x (1, 0, 0) in component "MM25 Y carriage and powered receiving deck"
  line L0 (-820, -186) -> (-310, -186)
  line L1 (-310, -186) -> (-310, -164)
  line L2 (-310, -164) -> (-820, -164)
  line L3 (-820, -164) -> (-820, -186)
extrude "Receiving deck side support" add sketch "Receiving deck side support sketch" along normal blind 20 separate body makes body 141 in component "MM25 Y carriage and powered receiving deck"
ref_plane "WorkPlane2" through (0, 0, -155) normal (0, 0, 1) x (1, 0, 0) in component "MM25 Y carriage and powered receiving deck"
sketch "Receiving deck side support sketch (1)" plane through (0, 0, -155) normal (0, 0, 1) x (1, 0, 0) in component "MM25 Y carriage and powered receiving deck"
  line L0 (-820, 164) -> (-310, 164)
  line L1 (-310, 164) -> (-310, 186)
  line L2 (-310, 186) -> (-820, 186)
  line L3 (-820, 186) -> (-820, 164)
extrude "Receiving deck side support (1)" add sketch "Receiving deck side support sketch (1)" along normal blind 20 separate body makes body 142 in component "MM25 Y carriage and powered receiving deck"
ref_plane "WorkPlane3" through (0, 0, -155) normal (0, 0, 1) x (1, 0, 0) in component "MM25 Y carriage and powered receiving deck"
sketch "Receiving deck cross member sketch" plane through (0, 0, -155) normal (0, 0, 1) x (1, 0, 0) in component "MM25 Y carriage and powered receiving deck"
  line L0 (-810, -165) -> (-790, -165)
  line L1 (-790, -165) -> (-790, 165)
  line L2 (-790, 165) -> (-810, 165)
  line L3 (-810, 165) -> (-810, -165)
extrude "Receiving deck cross member" add sketch "Receiving deck cross member sketch" along normal blind 20 separate body makes body 143 in component "MM25 Y carriage and powered receiving deck"
ref_plane "WorkPlane4" through (0, 0, -155) normal (0, 0, 1) x (1, 0, 0) in component "MM25 Y carriage and powered receiving deck"
sketch "Receiving deck cross member sketch (1)" plane through (0, 0, -155) normal (0, 0, 1) x (1, 0, 0) in component "MM25 Y carriage and powered receiving deck"
  line L0 (-575, -165) -> (-555, -165)
  line L1 (-555, -165) -> (-555, 165)
  line L2 (-555, 165) -> (-575, 165)
  line L3 (-575, 165) -> (-575, -165)
extrude "Receiving deck cross member (1)" add sketch "Receiving deck cross member sketch (1)" along normal blind 20 separate body makes body 144 in component "MM25 Y carriage and powered receiving deck"
ref_plane "WorkPlane5" through (0, 0, -155) normal (0, 0, 1) x (1, 0, 0) in component "MM25 Y carriage and powered receiving deck"
sketch "Receiving deck cross member sketch (2)" plane through (0, 0, -155) normal (0, 0, 1) x (1, 0, 0) in component "MM25 Y carriage and powered receiving deck"
  line L0 (-345, -165) -> (-325, -165)
  line L1 (-325, -165) -> (-325, 165)
  line L2 (-325, 165) -> (-345, 165)
  line L3 (-345, 165) -> (-345, -165)
extrude "Receiving deck cross member (2)" add sketch "Receiving deck cross member sketch (2)" along normal blind 20 separate body makes body 145 in component "MM25 Y carriage and powered receiving deck"
ref_plane "WorkPlane6" through (0, 0, -215) normal (0, 0, 1) x (1, 0, 0) in component "MM25 Y carriage and powered receiving deck"
sketch "Y bearing saddle sketch" plane through (0, 0, -215) normal (0, 0, 1) x (1, 0, 0) in component "MM25 Y carriage and powered receiving deck"
  line L0 (-822, -35) -> (-774, -35)
  line L1 (-774, -35) -> (-774, 35)
  line L2 (-774, 35) -> (-822, 35)
  line L3 (-822, 35) -> (-822, -35)
extrude "Y bearing saddle" add sketch "Y bearing saddle sketch" along normal blind 60 separate body makes body 146 in component "MM25 Y carriage and powered receiving deck"
ref_plane "WorkPlane7" through (0, 0, -206) normal (0, 0, 1) x (1, 0, 0) in component "MM25 Y carriage and powered receiving deck"
sketch "Y bearing clearance sketch" plane through (0, 0, -206) normal (0, 0, 1) x (1, 0, 0) in component "MM25 Y carriage and powered receiving deck"
  line L0 (-815, -40) -> (-781, -40)
  line L1 (-781, -40) -> (-781, 40)
  line L2 (-781, 40) -> (-815, 40)
  line L3 (-815, 40) -> (-815, -40)
extrude "Y bearing clearance" cut sketch "Y bearing clearance sketch" along normal blind 42 bodies 141 142 143 144 145 146 in component "MM25 Y carriage and powered receiving deck"
ref_plane "WorkPlane8" through (0, -195, 0) normal (0, 1, 0) x (0, 0, 1) in component "MM25 Y carriage and powered receiving deck"
sketch "Receiving deck roller sketch" plane through (0, -195, 0) normal (0, 1, 0) x (1, 0, 0) in component "MM25 Y carriage and powered receiving deck"
  circle A0 centre (-800, 136) radius 8
extrude "Receiving deck roller" add sketch "Receiving deck roller sketch" along normal blind 390 separate body makes body 147 in component "MM25 Y carriage and powered receiving deck"
ref_plane "WorkPlane9" through (0, -195, 0) normal (0, 1, 0) x (0, 0, 1) in component "MM25 Y carriage and powered receiving deck"
sketch "Receiving deck roller sketch (1)" plane through (0, -195, 0) normal (0, 1, 0) x (1, 0, 0) in component "MM25 Y carriage and powered receiving deck"
  circle A0 centre (-752, 136) radius 8
extrude "Receiving deck roller (1)" add sketch "Receiving deck roller sketch (1)" along normal blind 390 separate body makes body 148 in component "MM25 Y carriage and powered receiving deck"
ref_plane "WorkPlane10" through (0, -195, 0) normal (0, 1, 0) x (0, 0, 1) in component "MM25 Y carriage and powered receiving deck"
sketch "Receiving deck roller sketch (2)" plane through (0, -195, 0) normal (0, 1, 0) x (1, 0, 0) in component "MM25 Y carriage and powered receiving deck"
  circle A0 centre (-704, 136) radius 8
extrude "Receiving deck roller (2)" add sketch "Receiving deck roller sketch (2)" along normal blind 390 separate body makes body 149 in component "MM25 Y carriage and powered receiving deck"
ref_plane "WorkPlane11" through (0, -195, 0) normal (0, 1, 0) x (0, 0, 1) in component "MM25 Y carriage and powered receiving deck"
sketch "Receiving deck roller sketch (3)" plane through (0, -195, 0) normal (0, 1, 0) x (1, 0, 0) in component "MM25 Y carriage and powered receiving deck"
  circle A0 centre (-656, 136) radius 8
extrude "Receiving deck roller (3)" add sketch "Receiving deck roller sketch (3)" along normal blind 390 separate body makes body 150 in component "MM25 Y carriage and powered receiving deck"
ref_plane "WorkPlane12" through (0, -195, 0) normal (0, 1, 0) x (0, 0, 1) in component "MM25 Y carriage and powered receiving deck"
sketch "Receiving deck roller sketch (4)" plane through (0, -195, 0) normal (0, 1, 0) x (1, 0, 0) in component "MM25 Y carriage and powered receiving deck"
  circle A0 centre (-608, 136) radius 8
extrude "Receiving deck roller (4)" add sketch "Receiving deck roller sketch (4)" along normal blind 390 separate body makes body 151 in component "MM25 Y carriage and powered receiving deck"
ref_plane "WorkPlane13" through (0, -195, 0) normal (0, 1, 0) x (0, 0, 1) in component "MM25 Y carriage and powered receiving deck"
sketch "Receiving deck roller sketch (5)" plane through (0, -195, 0) normal (0, 1, 0) x (1, 0, 0) in component "MM25 Y carriage and powered receiving deck"
  circle A0 centre (-560, 136) radius 8
extrude "Receiving deck roller (5)" add sketch "Receiving deck roller sketch (5)" along normal blind 390 separate body makes body 152 in component "MM25 Y carriage and powered receiving deck"
ref_plane "WorkPlane14" through (0, -195, 0) normal (0, 1, 0) x (0, 0, 1) in component "MM25 Y carriage and powered receiving deck"
sketch "Receiving deck roller sketch (6)" plane through (0, -195, 0) normal (0, 1, 0) x (1, 0, 0) in component "MM25 Y carriage and powered receiving deck"
  circle A0 centre (-512, 136) radius 8
extrude "Receiving deck roller (6)" add sketch "Receiving deck roller sketch (6)" along normal blind 390 separate body makes body 153 in component "MM25 Y carriage and powered receiving deck"
ref_plane "WorkPlane15" through (0, -195, 0) normal (0, 1, 0) x (0, 0, 1) in component "MM25 Y carriage and powered receiving deck"
sketch "Receiving deck roller sketch (7)" plane through (0, -195, 0) normal (0, 1, 0) x (1, 0, 0) in component "MM25 Y carriage and powered receiving deck"
  circle A0 centre (-464, 136) radius 8
extrude "Receiving deck roller (7)" add sketch "Receiving deck roller sketch (7)" along normal blind 390 separate body makes body 154 in component "MM25 Y carriage and powered receiving deck"
ref_plane "WorkPlane16" through (0, -195, 0) normal (0, 1, 0) x (0, 0, 1) in component "MM25 Y carriage and powered receiving deck"